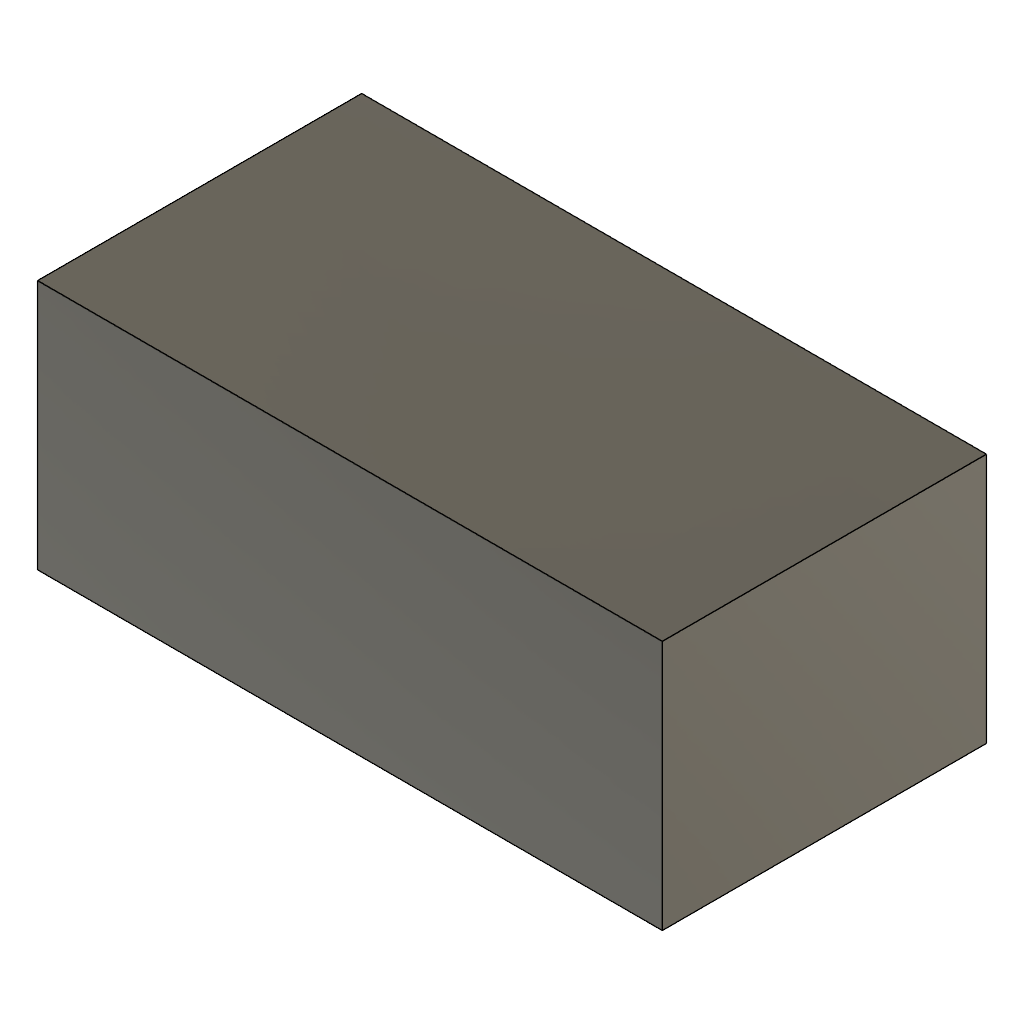
verbatim-awc03-webcam (Autodesk Fusion 360 design; units mm, degrees)
part number: 2026-10-24-11-47-56-049
Autodesk Fusion 360 part; units mm, degrees
sketch "webcam_footprint" plane through (0, 0, 0) normal (0, 0, 1) x (1, 0, 0)
  line L0 (60, 0) -> (166, 0)
  line L1 (166, 0) -> (166, 55)
  line L2 (166, 55) -> (60, 55)
  line L3 (60, 55) -> (60, 0)
  line L4 (1.75, 0) -> (22.5, 0) construction
  dimension "d6" = 60
  dimension "d7" = 106
  dimension "d8" = 55
  constraint horizontal L0
  constraint horizontal L2
  constraint vertical L1
  constraint vertical L3
  constraint coincident L0.start L4
  measures "d6" horizontal distance of origin L0.start
  measures "d7" horizontal distance of L0.start L0.end
  measures "d8" vertical distance of L0.end L1.end
extrude "Extrude1" add sketch "webcam_footprint" along normal blind 42.5
equation "d6 = webcam_offset"
equation "d7 = webcam_L"
equation "d8 = webcam_W"
equation "d9 = webcam_H"
equation "webcam_L = 106 mm" comment "Verbatim AWC-03 49580: length (datasheet LxWxH 106x55x42.5) - verify with caliper"
equation "webcam_W = 55 mm" comment "Verbatim AWC-03: W from datasheet - verify"
equation "webcam_H = 42.5 mm" comment "Verbatim AWC-03: H from datasheet - verify"
equation "webcam_offset = 60 mm" comment "Placement offset from XIAO along X (layout only)"
named bodies: "webcam_envelope"
